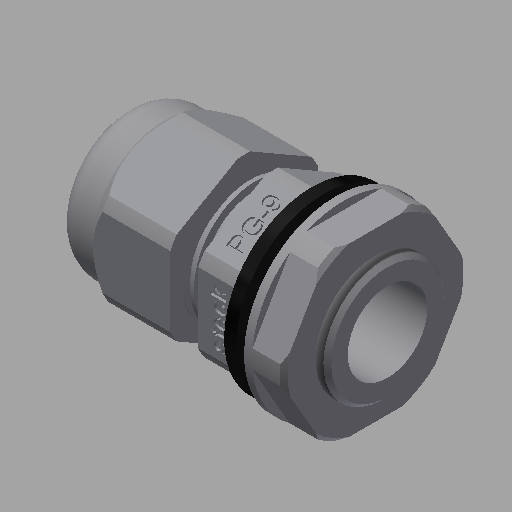
# Autodesk Inventor part: PRENSA CABO - 3-8
Saved by Autodesk Inventor 2022.2 (Build 262287030, 287C)
## iProperties
Created: 2012-10-23
Part Number: PRENSA CABO - 3-8
Document SubType Name: Modeling
Designer: CESAR
Density: 1 g/cm^3
Material: Genérico
Appearance: Padrão
Mass: 6.77902 g
Surface Area: 45.7905 cm^2
Volume: 6.77902 cm^3
Author: CESAR
Autodesk Inventor part; units mm, degrees
ref_plane "YZ Plane" through (0, 0, 0) normal (1, 0, 0) x (0, 1, 0)
ref_plane "XZ Plane" through (0, 0, 0) normal (0, 1, 0) x (-1, 0, 0)
ref_plane "XY Plane" through (0, 0, 0) normal (0, 0, 1) x (1, 0, 0)
sketch "Sketch1" plane through (0, 0, 0) normal (0, 0, 1) x (1, 0, 0)
  line L0 (0, 13.8) -> (0, -2.3) projected
  line L1 (-7.3456, 0) -> (39.7243, 0) projected
  line L2 (0, 0) -> (33, 0)
  line L3 (0, 4.75) -> (0, 6)
  line L4 (3, 9) -> (5, 9)
  line L5 (5, 9) -> (5, 10.25)
  line L6 (5, 10.25) -> (15, 10.25)
  line L7 (15, 10.25) -> (15, 6.75)
  line L8 (15, 6.75) -> (18.5, 6.75)
  line L9 (18.5, 6.75) -> (18.5, 10.25)
  line L10 (18.5, 10.25) -> (23.5, 10.25)
  line L11 (23.5, 10.25) -> (23.5, 11)
  line L12 (23.5, 11) -> (25, 11)
  line L13 (25, 11) -> (25, 7.55)
  line L14 (25, 7.55) -> (26.5, 7.55)
  line L15 (26.5, 7.55) -> (26.5, 11.5)
  line L16 (26.5, 11.5) -> (31, 11.5)
  line L17 (31.5, 11) -> (31.5, 7.55)
  line L18 (31.5, 7.55) -> (33, 7.55)
  line L19 (33, 7.55) -> (33, 5)
  line L20 (33, 5) -> (12, 5)
  line L21 (12, 5) -> (4.5, 3.25)
  line L22 (4.5, 3.25) -> (4.5, 4)
  line L23 (4.5, 4) -> (4, 4)
  line L24 (4, 4) -> (4, 6.5)
  line L25 (4, 6.5) -> (2.5, 4.25)
  line L26 (2.5, 4.25) -> (0.5, 4.25)
  arc A0 (3, 9) -> (0, 6) centre (3, 6) ccw
  arc A1 (0, 4.75) -> (0.5, 4.25) centre (0.5, 4.75) ccw
  line L27 (31, 11.5) -> (31.5, 11)
  point P0 (0, 9)
  point P1 (31.5, 11.5)
  point P2 (0, 4.25)
  point P3 (33, 6.275)
  point P4 (10, 10.25)
  point P5 (21, 10.25)
  point P6 (25.75, 7.55)
  point P7 (32.25, 7.55)
  dimension "d0" = 23
  dimension "d1" = 15.1
  dimension "d2" = 10
  dimension "d3" = 22
  dimension "d4" = 20.5
  dimension "d5" = 13.5
  dimension "d6" = 18
  dimension "d7" = 8.5
  dimension "d8" = 8
  dimension "d9" = 6.5
  dimension "d10" = 15
  dimension "d11" = 10
  dimension "d12" = 3.5
  dimension "d13" = 33
  dimension "d14" = 5
  dimension "d15" = 1.5
  dimension "d16" = 1.5
  dimension "d17" = 5
  dimension "d18" = 21
  dimension "d19" = 4.5
  dimension "d20" = 4
  dimension "d21" = 2.5
  dimension "d22" = 13
  dimension "d23" = 3
  dimension "d24" = 0.5
  dimension "d25" = 0.5
  dimension "d26" = 0.5
  constraints: 52 end point, 17 parallel, 9 point on line, 5 midpoint, 4 perpendicular, 4 point on circle, 4 tangent, 2 centre point, 2 horizontal alignment, 1 vertical alignment
  measures "d0" diameter of L16 L2
  measures "d1" diameter of L18 L2
  measures "d2" diameter of L20 L2
  measures "d3" diameter of L12 L2
  measures "d4" diameter of L10 L2
  measures "d5" diameter of L8 L2
  measures "d6" diameter of L4 L2
  measures "d7" diameter of L26 L2
  measures "d8" diameter of L23 L2
  measures "d9" diameter of L21.end L2
  measures "d10" distance between parallel lines of L3 L7
  measures "d11" distance of L5.end L6.end
  measures "d12" distance between parallel lines of L7 L9
  measures "d13" distance between parallel lines of L0 L19
  measures "d14" distance of L15.end point (31.5, 11.5)
  measures "d15" distance of L13.end L14.end
  measures "d16" distance of L11.end L12.end
  measures "d17" distance of L9.end L10.end
  measures "d18" distance of L19.end L20.end
  measures "d19" distance between parallel lines of L0 L22
  measures "d20" distance between parallel lines of L0 L24
  measures "d21" distance of L25.end point (0, 4.25)
  measures "d22" diameter of L24.end L2
  measures "d23" radius of A0
  measures "d24" radius of A1
  measures "d25" distance of L16.end point (31.5, 11.5)
  measures "d26" distance of L17.start point (31.5, 11.5)
revolve "Revolution1" add sketch "Sketch1" angle 360 about axis through (0, 0, 0) along (1, 0, 0)
sketch "Sketch2" plane through (5, 0, 0) normal (-1, 0, 0) x (0, 0, 1)
  circle A0 centre (0, 0) radius 10.25 projected
  circle A1 centre (0, 0) radius 9 projected
  line L0 (9.25, -5.3405) -> (0, -10.681)
  line L1 (0, -10.681) -> (-9.25, -5.3405)
  line L2 (-9.25, -5.3405) -> (-9.25, 5.3405)
  line L3 (-9.25, 5.3405) -> (0, 10.681)
  line L4 (0, 10.681) -> (9.25, 5.3405)
  line L5 (9.25, 5.3405) -> (9.25, -5.3405)
  arc A2 (9.25, -4.4159) -> (9.25, 4.4159) centre (0, 0) ccw
  arc A3 (0.8007, -10.2187) -> (8.4493, -5.8028) centre (0, 0) ccw
  arc A4 (-8.4493, -5.8028) -> (-0.8007, -10.2187) centre (0, 0) ccw
  arc A5 (-9.25, 4.4159) -> (-9.25, -4.4159) centre (0, 0) ccw
  arc A6 (-0.8007, 10.2187) -> (-8.4493, 5.8028) centre (0, 0) ccw
  arc A7 (8.4493, 5.8028) -> (0.8007, 10.2187) centre (0, 0) ccw
  dimension "d28" = 18.5
  constraints: 12 end point, 12 point on circle, 12 point on line, 6 centre point, 1 coincident, 1 vertical alignment, 32 other
  measures "d28" distance between parallel lines of L2 L5
extrude "Extrusion1" cut sketch "Sketch2" against normal up to surface (18.5 mm away) contours A0 L5 | L4 A0 | A0 L0 | L3 A0 | A0 L1 | L2 A0
sketch "Sketch3" plane through (0, 0, 0) normal (0, 0, 1) x (1, 0, 0)
  line L0 (5, 10.2187) -> (5, 10.25) projected
  line L1 (5, 10.2187) -> (5, 5.8028) projected
  line L2 (5, 10.25) -> (15, 10.25) projected
  line L3 (3, 9) -> (5, 9) projected
  line L4 (5, 9) -> (5, 10.25)
  line L5 (5, 10.25) -> (6.5, 10.25)
  line L6 (5, 9) -> (6.5, 10.25)
  line L7 (-6.6, 0) -> (39.6, 0) projected
  point P0 (0, 0)
  dimension "d31" = 1.5
  constraints: 6 end point, 1 collinear, 1 point on line
  measures "d31" distance of L2.start L5.end
revolve "Revolution2" cut sketch "Sketch3" angle 360 about axis through (-10, 0, 0) along (1, 0, 0)
sketch "Sketch4" plane through (31.5, 0, 0) normal (1, 0, 0) x (0, 0, -1)
  circle A0 centre (0, 0) radius 11.5 projected
  line L0 (6.0622, 10.5) -> (12.1244, 0)
  line L1 (12.1244, 0) -> (6.0622, -10.5)
  line L2 (6.0622, -10.5) -> (-6.0622, -10.5)
  line L3 (-6.0622, -10.5) -> (-12.1244, 0)
  line L4 (-12.1244, 0) -> (-6.0622, 10.5)
  line L5 (-6.0622, 10.5) -> (6.0622, 10.5)
  arc A1 (4.6904, 10.5) -> (-4.6904, 10.5) centre (0, 0) ccw
  arc A2 (11.4385, 1.188) -> (6.7481, 9.312) centre (0, 0) ccw
  arc A3 (6.7481, -9.312) -> (11.4385, -1.188) centre (0, 0) ccw
  arc A4 (-4.6904, -10.5) -> (4.6904, -10.5) centre (0, 0) ccw
  arc A5 (-11.4385, -1.188) -> (-6.7481, -9.312) centre (0, 0) ccw
  arc A6 (-6.7481, 9.312) -> (-11.4385, 1.188) centre (0, 0) ccw
  point P0 (0, 10.5)
  dimension "d33" = 21
  constraints: 12 end point, 12 point on circle, 12 point on line, 6 centre point, 1 coincident, 1 midpoint, 1 vertical alignment, 32 other
  measures "d33" distance between parallel lines of L2 L5
extrude "Extrusion2" cut sketch "Sketch4" against normal blind 4 contours L0 A0 | A0 L1 | L5 A0 | A0 L2 | L4 A0 | A0 L3
sketch "Sketch5" plane through (0, 0, 0) normal (0, 0, 1) x (1, 0, 0)
  line L0 (18.5, 10.2187) -> (18.5, 5.8028) projected
  line L1 (15, 6.75) -> (18.5, 6.75) projected
  line L2 (18.6, 6.75) -> (18.6, 7.75)
  line L3 (18.6, 7.75) -> (19.1, 7.75)
  line L4 (19.1, 7.75) -> (19.1, 6.75)
  line L5 (19.1, 6.75) -> (18.6, 6.75)
  point P0 (0, 0)
  point P1 (16.75, 6.75)
  point P2 (18.85, 6.75)
  dimension "d36" = 0.1
  dimension "d37" = 0.5
  dimension "d38" = 1
  constraints: 8 end point, 2 midpoint, 2 parallel, 2 perpendicular, 1 horizontal alignment
  measures "d36" distance between parallel lines of L0 L2
  measures "d37" distance of L2.end L3.end
  measures "d38" distance of L3.end L4.end
coil "Coil1" sketch "Sketch5" operation add axis through (-10, 0, 0) along (-1, 0, 0) pitch 1.5 turns 3 hand right
sketch "Sketch6" plane through (18.5, -4.4159, 9.25) normal (0, 0, 1) x (1, 0, 0)
  line L0 (0, 0) -> (0, 8.8318) projected
  line L1 (0, 8.8318) -> (5, 8.8318) projected
  line L2 (1.475, 0.8554) -> (1.475, 7.9763) construction
  line L3 (1.475, 7.9763) -> (3.525, 7.9763) construction
  line L4 (3.525, 7.9763) -> (3.525, 0.8554) construction
  line L5 (3.525, 0.8554) -> (1.475, 0.8554) construction
  line L6 (3.0604, 0.921) -> (3.0025, 1.3051)
  spline S0 degree 2 poles (3.0025, 1.3051) (3.1138, 1.3295) (3.2296, 1.4804) (3.2296, 1.6146) knots 0 0 0 1 2 2 2
  spline S1 degree 2 poles (3.2296, 1.6146) (3.2296, 1.764) (3.1747, 1.8387) knots 0 0 0 1 1 1
  spline S2 degree 2 poles (3.1747, 1.8387) (3.1366, 1.889) (3.0726, 1.889) knots 0 0 0 1 1 1
  spline S3 degree 2 poles (3.0726, 1.889) (3.0299, 1.889) (3.0009, 1.8615) knots 0 0 0 1 1 1
  spline S4 degree 2 poles (3.0009, 1.8615) (2.9735, 1.8326) (2.9506, 1.7335) knots 0 0 0 1 1 1
  spline S5 degree 2 poles (2.9506, 1.7335) (2.8485, 1.2701) (2.7631, 1.1466) knots 0 0 0 1 1 1
  spline S6 degree 2 poles (2.7631, 1.1466) (2.6458, 0.9743) (2.4384, 0.9743) knots 0 0 0 1 1 1
  spline S7 degree 2 poles (2.4384, 0.9743) (2.2494, 0.9743) (1.9933, 1.2716) (1.9933, 1.5841) knots 0 0 0 1 2 2 2
  spline S8 degree 2 poles (1.9933, 1.5841) (1.9933, 1.8814) (2.1869, 2.1695) (2.3775, 2.2243) knots 0 0 0 1 2 2 2
  line L7 (2.3775, 2.2243) -> (2.4445, 1.8631)
  spline S9 degree 2 poles (2.4445, 1.8631) (2.3592, 1.8402) (2.2692, 1.7106) (2.2692, 1.5902) knots 0 0 0 1 2 2 2
  spline S10 degree 2 poles (2.2692, 1.5902) (2.2692, 1.4393) (2.3119, 1.3753) knots 0 0 0 1 1 1
  spline S11 degree 2 poles (2.3119, 1.3753) (2.3409, 1.3311) (2.3897, 1.3311) knots 0 0 0 1 1 1
  spline S12 degree 2 poles (2.3897, 1.3311) (2.4293, 1.3311) (2.4583, 1.3692) knots 0 0 0 1 1 1
  spline S13 degree 2 poles (2.4583, 1.3692) (2.4964, 1.421) (2.6351, 2.0323) (2.7372, 2.1527) knots 0 0 0 1 2 2 2
  spline S14 degree 2 poles (2.7372, 2.1527) (2.8394, 2.2731) (3.0223, 2.2731) knots 0 0 0 1 1 1
  spline S15 degree 2 poles (3.0223, 2.2731) (3.2205, 2.2731) (3.507, 1.9408) (3.507, 1.6146) knots 0 0 0 1 2 2 2
  spline S16 degree 2 poles (3.507, 1.6146) (3.507, 1.3189) (3.2662, 0.9743) (3.0604, 0.921) knots 0 0 0 1 2 2 2
  line L8 (2.0253, 3.2731) -> (2.3302, 3.2731)
  line L9 (2.3302, 3.2731) -> (2.3302, 3.0109)
  line L10 (2.3302, 3.0109) -> (2.9141, 3.0109)
  spline S17 degree 2 poles (2.9141, 3.0109) (3.0909, 3.0109) (3.1503, 3.0262) (3.1884, 3.0795) (3.1884, 3.1176) knots 0 0 0 1 2 3 3 3
  spline S18 degree 2 poles (3.1884, 3.1176) (3.1884, 3.171) (3.1519, 3.2731) knots 0 0 0 1 1 1
  line L11 (3.1519, 3.2731) -> (3.4491, 3.3051)
  spline S19 degree 2 poles (3.4491, 3.3051) (3.507, 3.171) (3.507, 3.0018) knots 0 0 0 1 1 1
  spline S20 degree 2 poles (3.507, 3.0018) (3.507, 2.8981) (3.4369, 2.732) (3.3272, 2.6542) (3.2327, 2.639) knots 0 0 0 1 2 3 3 3
  spline S21 degree 2 poles (3.2327, 2.639) (3.1656, 2.6268) (2.9628, 2.6268) knots 0 0 0 1 1 1
  line L12 (2.9628, 2.6268) -> (2.3302, 2.6268)
  line L13 (2.3302, 2.6268) -> (2.3302, 2.4515)
  line L14 (2.3302, 2.4515) -> (2.0253, 2.4515)
  line L15 (2.0253, 2.4515) -> (2.0253, 2.6268)
  line L16 (2.0253, 2.6268) -> (1.7372, 2.6268)
  line L17 (1.7372, 2.6268) -> (1.5116, 3.0109)
  line L18 (1.5116, 3.0109) -> (2.0253, 3.0109)
  line L19 (2.0253, 3.0109) -> (2.0253, 3.2731)
  line L20 (3.0131, 4.3783) -> (3.0772, 4.7609)
  spline S22 degree 2 poles (3.0772, 4.7609) (3.2875, 4.6878) (3.507, 4.3692) (3.507, 4.1298) knots 0 0 0 1 2 2 2
  spline S23 degree 2 poles (3.507, 4.1298) (3.507, 3.7518) (3.2601, 3.5704) knots 0 0 0 1 1 1
  spline S24 degree 2 poles (3.2601, 3.5704) (3.0619, 3.4271) (2.7616, 3.4271) knots 0 0 0 1 1 1
  spline S25 degree 2 poles (2.7616, 3.4271) (2.4003, 3.4271) (1.9933, 3.8036) (1.9933, 4.0917) knots 0 0 0 1 2 2 2
  spline S26 degree 2 poles (1.9933, 4.0917) (1.9933, 4.4149) (2.4202, 4.7884) (2.8607, 4.7808) knots 0 0 0 1 2 2 2
  line L21 (2.8607, 4.7808) -> (2.8607, 3.8204)
  spline S27 degree 2 poles (2.8607, 3.8204) (3.0314, 3.825) (3.2205, 4.0018) (3.2205, 4.1344) knots 0 0 0 1 2 2 2
  spline S28 degree 2 poles (3.2205, 4.1344) (3.2205, 4.2243) (3.1229, 4.3463) (3.0131, 4.3783) knots 0 0 0 1 2 2 2
  spline S29 degree 2 poles (2.6259, 4.3997) (2.4598, 4.3951) (2.286, 4.232) (2.286, 4.1146) knots 0 0 0 1 2 2 2
  spline S30 degree 2 poles (2.286, 4.1146) (2.286, 3.9896) (2.3775, 3.9073) knots 0 0 0 1 1 1
  spline S31 degree 2 poles (2.3775, 3.9073) (2.4689, 3.8265) (2.6259, 3.8265) knots 0 0 0 1 1 1
  line L22 (2.6259, 3.8265) -> (2.6259, 4.3997)
  line L23 (2.4537, 6.3539) -> (2.5223, 5.9759)
  spline S32 degree 2 poles (2.5223, 5.9759) (2.4095, 5.9576) (2.2952, 5.8219) (2.2952, 5.7137) knots 0 0 0 1 2 2 2
  spline S33 degree 2 poles (2.2952, 5.7137) (2.2952, 5.5719) (2.4933, 5.4012) (2.725, 5.4012) knots 0 0 0 1 2 2 2
  spline S34 degree 2 poles (2.725, 5.4012) (2.9827, 5.4012) (3.1945, 5.575) (3.1945, 5.7198) knots 0 0 0 1 2 2 2
  spline S35 degree 2 poles (3.1945, 5.7198) (3.1945, 5.8295) (3.0695, 5.9683) (2.9186, 5.9972) knots 0 0 0 1 2 2 2
  line L24 (2.9186, 5.9972) -> (2.9827, 6.3737)
  spline S36 degree 2 poles (2.9827, 6.3737) (3.2418, 6.3158) (3.507, 5.982) (3.507, 5.703) knots 0 0 0 1 2 2 2
  spline S37 degree 2 poles (3.507, 5.703) (3.507, 5.3859) (3.1061, 5.0079) (2.7509, 5.0079) knots 0 0 0 1 2 2 2
  spline S38 degree 2 poles (2.7509, 5.0079) (2.3927, 5.0079) (1.9933, 5.3859) (1.9933, 5.7091) knots 0 0 0 1 2 2 2
  spline S39 degree 2 poles (1.9933, 5.7091) (1.9933, 5.9743) (2.2205, 6.2853) (2.4537, 6.3539) knots 0 0 0 1 2 2 2
  line L25 (3.475, 6.6329) -> (1.475, 6.6329)
  line L26 (1.475, 6.6329) -> (1.475, 7.017)
  line L27 (1.475, 7.017) -> (2.536, 7.017)
  line L28 (2.536, 7.017) -> (2.0253, 7.4652)
  line L29 (2.0253, 7.4652) -> (2.0253, 7.9378)
  line L30 (2.0253, 7.9378) -> (2.5558, 7.4423)
  line L31 (2.5558, 7.4423) -> (3.475, 7.9728)
  line L32 (3.475, 7.9728) -> (3.475, 7.5597)
  line L33 (3.475, 7.5597) -> (2.8241, 7.1939)
  line L34 (2.8241, 7.1939) -> (3.0116, 7.017)
  line L35 (3.0116, 7.017) -> (3.475, 7.017)
  line L36 (3.475, 7.017) -> (3.475, 6.6329)
  point P0 (-18.5, 4.4159)
  point P1 (2.5, 7.9763)
  point P2 (2.5, 8.8318)
  point P3 (1.475, 4.4159)
  point P4 (0, 4.4159)
  constraints: 4 midpoint, 1 horizontal alignment, 1 vertical alignment, 2 other
extrude "Extrusion3" cut sketch "Sketch6" against normal blind 0.3
sketch "Sketch7" plane through (18.5, 5.8028, 8.4493) normal (0, 0.8660254, 0.5) x (1, 0, 0)
  line L0 (0, 0) -> (0, 8.8318) projected
  line L1 (0, 8.8318) -> (5, 8.8318) projected
  line L2 (1.417, 1.1406) -> (1.417, 7.6912) construction
  line L3 (1.417, 7.6912) -> (3.583, 7.6912) construction
  line L4 (3.583, 7.6912) -> (3.583, 1.1406) construction
  line L5 (3.583, 1.1406) -> (1.417, 1.1406) construction
  line L6 (3.4521, 1.3555) -> (1.4521, 1.3555)
  line L7 (1.4521, 1.3555) -> (1.4521, 2.1101)
  spline S0 degree 2 poles (1.4521, 2.1101) (1.4521, 2.3098) (1.4719, 2.415) knots 0 0 0 1 1 1
  spline S1 degree 2 poles (1.4719, 2.415) (1.4963, 2.5628) (1.6335, 2.761) (1.882, 2.883) (2.0314, 2.883) knots 0 0 0 1 2 3 3 3
  spline S2 degree 2 poles (2.0314, 2.883) (2.2859, 2.883) (2.6396, 2.5583) (2.6396, 2.1345) knots 0 0 0 1 2 2 2
  line L8 (2.6396, 2.1345) -> (2.6396, 1.6208)
  line L9 (2.6396, 1.6208) -> (3.4521, 1.6208)
  line L10 (3.4521, 1.6208) -> (3.4521, 1.3555)
  line L11 (2.4033, 1.6208) -> (2.4033, 2.1375)
  spline S3 degree 2 poles (2.4033, 2.1375) (2.4033, 2.3952) (2.2128, 2.6101) (2.039, 2.6101) knots 0 0 0 1 2 2 2
  spline S4 degree 2 poles (2.039, 2.6101) (1.914, 2.6101) (1.7341, 2.4836) (1.7067, 2.3799) knots 0 0 0 1 2 2 2
  spline S5 degree 2 poles (1.7067, 2.3799) (1.6884, 2.3128) (1.6884, 2.133) knots 0 0 0 1 1 1
  line L12 (1.6884, 2.133) -> (1.6884, 1.6208)
  line L13 (1.6884, 1.6208) -> (2.4033, 1.6208)
  line L14 (2.6686, 4.1573) -> (2.4323, 4.1573)
  line L15 (2.4323, 4.1573) -> (2.4323, 5.0034)
  line L16 (2.4323, 5.0034) -> (3.1731, 5.0034)
  spline S6 degree 2 poles (3.1731, 5.0034) (3.3286, 4.8083) (3.4856, 4.3936) (3.4856, 4.1756) knots 0 0 0 1 2 2 2
  spline S7 degree 2 poles (3.4856, 4.1756) (3.4856, 3.8814) (3.2326, 3.3997) (2.7555, 3.1543) (2.4613, 3.1543) knots 0 0 0 1 2 3 3 3
  spline S8 degree 2 poles (2.4613, 3.1543) (2.1686, 3.1543) (1.6625, 3.3982) (1.417, 3.857) (1.417, 4.1558) knots 0 0 0 1 2 3 3 3
  spline S9 degree 2 poles (1.417, 4.1558) (1.417, 4.3723) (1.5573, 4.7229) (1.8088, 4.9211) (2.0116, 4.9729) knots 0 0 0 1 2 3 3 3
  line L17 (2.0116, 4.9729) -> (2.0771, 4.7351)
  spline S10 degree 2 poles (2.0771, 4.7351) (1.9247, 4.6894) (1.7494, 4.5567) (1.6442, 4.3083) (1.6442, 4.1573) knots 0 0 0 1 2 3 3 3
  spline S11 degree 2 poles (1.6442, 4.1573) (1.6442, 3.9759) (1.7539, 3.7107) (1.9353, 3.5491) (2.042, 3.5034) knots 0 0 0 1 2 3 3 3
  spline S12 degree 2 poles (2.042, 3.5034) (2.228, 3.4272) (2.4445, 3.4272) knots 0 0 0 1 1 1
  spline S13 degree 2 poles (2.4445, 3.4272) (2.7113, 3.4272) (3.0725, 3.6116) (3.2463, 3.9637) (3.2463, 4.1604) knots 0 0 0 1 2 3 3 3
  spline S14 degree 2 poles (3.2463, 4.1604) (3.2463, 4.3327) (3.1137, 4.6604) (3.039, 4.7442) knots 0 0 0 1 2 2 2
  line L18 (3.039, 4.7442) -> (2.6686, 4.7442)
  line L19 (2.6686, 4.7442) -> (2.6686, 4.1573)
  line L20 (2.8515, 5.2656) -> (2.6045, 5.2656)
  line L21 (2.6045, 5.2656) -> (2.6045, 6.0217)
  line L22 (2.6045, 6.0217) -> (2.8515, 6.0217)
  line L23 (2.8515, 6.0217) -> (2.8515, 5.2656)
  line L24 (2.9887, 6.261) -> (2.9673, 6.4973)
  spline S15 degree 2 poles (2.9673, 6.4973) (3.1335, 6.5278) (3.2844, 6.697) (3.2844, 6.8281) knots 0 0 0 1 2 2 2
  spline S16 degree 2 poles (3.2844, 6.8281) (3.2844, 6.9409) (3.1808, 7.1131) (3.007, 7.2214) (2.7128, 7.2945) (2.5588, 7.2945) knots 0 0 0 1 2 3 4 4 4
  spline S17 degree 2 poles (2.5588, 7.2945) (2.5436, 7.2945) (2.51, 7.293) knots 0 0 0 1 1 1
  spline S18 degree 2 poles (2.51, 7.293) (2.6274, 7.2198) (2.7738, 6.9653) (2.7738, 6.8159) knots 0 0 0 1 2 2 2
  spline S19 degree 2 poles (2.7738, 6.8159) (2.7738, 6.5674) (2.414, 6.2244) (2.1198, 6.2244) knots 0 0 0 1 2 2 2
  spline S20 degree 2 poles (2.1198, 6.2244) (1.8149, 6.2244) (1.4445, 6.5827) (1.4445, 6.8525) knots 0 0 0 1 2 2 2
  spline S21 degree 2 poles (1.4445, 6.8525) (1.4445, 7.0476) (1.6548, 7.3708) (2.0436, 7.5384) (2.4109, 7.5384) knots 0 0 0 1 2 3 3 3
  spline S22 degree 2 poles (2.4109, 7.5384) (2.7951, 7.5384) (3.2478, 7.3723) (3.4856, 7.043) (3.4856, 6.822) knots 0 0 0 1 2 3 3 3
  spline S23 degree 2 poles (3.4856, 6.822) (3.4856, 6.5887) (3.225, 6.2915) (2.9887, 6.261) knots 0 0 0 1 2 2 2
  spline S24 degree 2 poles (2.1076, 7.2656) (1.8957, 7.2656) (1.6472, 7.0415) (1.6472, 6.883) knots 0 0 0 1 2 2 2
  spline S25 degree 2 poles (1.6472, 6.883) (1.6472, 6.7183) (1.914, 6.4775) (2.1274, 6.4775) knots 0 0 0 1 2 2 2
  spline S26 degree 2 poles (2.1274, 6.4775) (2.318, 6.4775) (2.5573, 6.7061) (2.5573, 6.8769) knots 0 0 0 1 2 2 2
  spline S27 degree 2 poles (2.5573, 6.8769) (2.5573, 7.0461) (2.318, 7.2656) (2.1076, 7.2656) knots 0 0 0 1 2 2 2
  point P0 (-18.5, 4.4159)
  point P1 (2.5, 7.6912)
  point P2 (2.5, 8.8318)
  point P3 (1.417, 4.4159)
  point P4 (0, 4.4159)
  constraints: 4 midpoint, 1 horizontal alignment, 1 vertical alignment, 2 other
extrude "Extrusion4" cut sketch "Sketch7" against normal blind 0.3
thread "Thread1" size "1/2" designation "1/2 - 14 NPT" standard "NPT" full length
thread "Thread2" size "1/2" designation "1/2 - 14 NPT" standard "NPT" full length
chamfer "Chamfer1" distance 0.5 angle 45 1 edges at (33, -7.55, 0)
equation "\"d26\" = d25"
body "Solid1"
